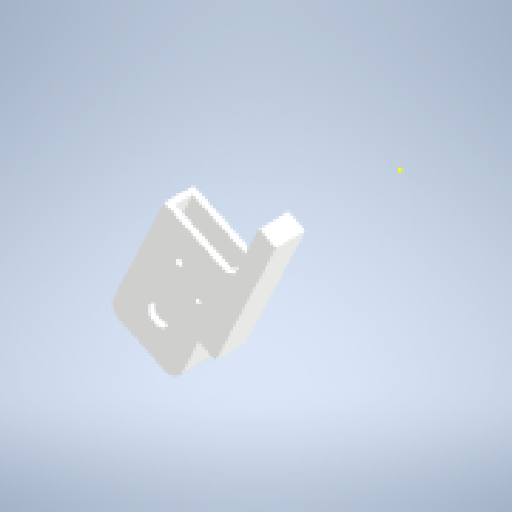
# Autodesk Inventor part: носок
Saved by Autodesk Inventor 2024.2 (Build 282272000, 272)
## iProperties
Created: 2026-10-18
Material: PA-CF
Document SubType Name: Modeling
Designer: katya_notebook
Density: 1.18 g/cm^3
Appearance: Типовые
Author: katya_notebook
Autodesk Inventor part; units mm, degrees
ref_plane "YZ Plane" through (0, 0, 0) normal (1, 0, 0) x (0, 1, 0)
ref_plane "РабПлоскость1" through (0, -0.018426, 0) normal (0, 0, 1) x (1, 0, 0)
sketch "Эскиз1" plane through (0, -0.018426, 0) normal (0, 0, 1) x (1, 0, 0)
  line L0 (-65.689125, -37.064541) -> (-83.531835, -74.877942)
  line L1 (-83.531835, -74.877942) -> (-61.82685, -85.119701)
  line L2 (-61.82685, -85.119701) -> (-43.98414, -47.3063)
  line L3 (-43.98414, -47.3063) -> (-65.689125, -37.064541)
  arc A0 (-77.192404, -71.183023) -> (-58.408034, -73.187635) centre (-67.451778, -68.920236) ccw
  line L4 (-45.566796, -46.559505) -> (-62.556025, -82.564158)
  line L5 (-62.556025, -82.564158) -> (-81.0957, -73.815989)
  line L6 (-81.0957, -73.815989) -> (-64.10647, -37.811336)
  circle A1 centre (-67.451778, -68.920236) radius 10.25
  point P0 (0, 0.018426)
  point P1 (-52.153804, -59.933275)
  point P2 (-45.566796, -46.559505)
  point P3 (-71.825862, -78.190073)
  point P4 (-73.75402, -77.003815)
  point P5 (-76.721615, -64.546151)
  point P6 (-58.181941, -73.29432)
  dimension "d2" = 0
  dimension "d3" = 2
  dimension "d4" = 12.25
  dimension "d5" = 2
  dimension "d20" = 20.5
  dimension "d21" = 10.25
  dimension "d22" = 20.5
  constraints: 14 end point, 3 perpendicular, 2 parallel, 1 centre point, 1 coincident, 1 point on line
  measures "d2" distance from line of L3 L4.start
  measures "d3" distance from line of point (-52.154, -59.933) L2
  measures "d4" distance from line of A0.centre L1
  measures "d5" distance between parallel lines of L1 L5
  measures "d20" diameter of A1
  measures "d21" distance from line of A0.centre L6
  measures "d22" distance between parallel lines of L6 L4
extrude "Выдавливание1" add sketch "Эскиз1" along normal blind 2 and the other way blind 7.5 contours L3 L6 L5 L4 L2 L1 L0
ref_plane "РабПлоскость2" through (0, -0.018426, 0) normal (0, 0, 1) x (1, 0, 0)
sketch "Эскиз2" plane through (0, -0.018426, 2) normal (0, 0, 1) x (1, 0, 0)
  circle A0 centre (-67.451778, -68.920236) radius 2.5
  circle A1 centre (-60.722907, -51.152512) radius 1
  line L0 (-45.566796, -46.559505) -> (-62.556025, -82.564158)
  line L1 (-81.0957, -73.815989) -> (-64.10647, -37.811336)
  circle A2 centre (-67.451778, -68.920236) radius 10.25
  line L2 (-64.10647, -37.811336) -> (-45.566796, -46.559505)
  line L3 (-62.556025, -82.564158) -> (-81.0957, -73.815989)
  point P0 (0, 0.018426)
  point P1 (-62.554737, -82.561427)
  constraints: 2 end point, 1 centre point, 1 coincident, 1 point on line, 1 tangent
sketch "Эскиз4" plane through (0, -0.018426, -7.5) normal (0, 0, -1) x (-1, 0, 0)
  circle A0 centre (60.722907, -51.152512) radius 1
  circle A1 centre (67.451778, -68.920236) radius 2.5
  line L0 (64.10647, -37.811336) -> (81.0957, -73.815989)
  line L1 (81.0957, -73.815989) -> (62.556025, -82.564158)
  line L2 (62.556025, -82.564158) -> (45.566796, -46.559505)
  line L3 (64.10647, -37.811336) -> (45.566796, -46.559505)
  point P0 (0, 0.018426)
  point P1 (45.686204, -46.226727)
  constraints: 2 end point
fillet "Сопряжение1" radius 4 2 edges at (-83.5318, -74.8964, -2.75) (-61.8268, -85.1381, -2.75)
sketch "Эскиз5" plane through (0, -0.018426, -7.5) normal (0, 0, -1) x (-1, 0, 0)
  point P0 (0, 0.018426)
extrude "Выдавливание5" add sketch "Эскиз2" against normal blind 2
extrude "Выдавливание6" add sketch "Эскиз4" against normal blind 2
sketch "Эскиз7" plane through (0, -0.018426, 2) normal (0, 0, 1) x (1, 0, 0)
  line L0 (-60.11989, -81.502204) -> (-43.98414, -47.3063)
  line L1 (-43.98414, -47.3063) -> (-35.449341, -29.218813)
  line L2 (-35.449341, -29.218813) -> (-30.023095, -31.779253)
  line L3 (-30.023095, -31.779253) -> (-49.226393, -72.476099)
  line L4 (-49.226393, -72.476099) -> (-54.652639, -69.91566)
  point P0 (0, 0.018426)
  dimension "d27" = 25
  dimension "d29" = 45
  dimension "d30" = 6
  constraints: 8 end point, 4 perpendicular, 1 point on line
  measures "d27" distance from line of L4 L0.end
  measures "d29" distance between parallel lines of L4 L2
  measures "d30" distance between parallel lines of L3 L0
extrude "Выдавливание7" add sketch "Эскиз7" against normal up to surface (9.5 mm away)
sketch "Эскиз8" plane through (0, -0.018426, 2) normal (0, 0, 1) x (1, 0, 0)
  circle A0 centre (-54.681018, -58.844901) radius 0.75
  line L0 (-43.98414, -47.3063) -> (-65.689125, -37.064541)
  line L1 (-62.556025, -82.564158) -> (-45.566796, -46.559505)
  point P0 (0, 0.018426)
  dimension "d33" = 1.5
  dimension "d34" = 15
  dimension "d35" = 3
  constraints: 1 centre point
  measures "d33" diameter of A0
  measures "d34" distance from line of L0 A0.centre
  measures "d35" distance from line of A0.centre L1
extrude "Выдавливание8" cut sketch "Эскиз8" against normal blind 10
chamfer "Фаска2" distance 2 angle 45 1 edges at (-43.9841, -47.3247, -2.75)
sketch "Эскиз9" plane through (0, -0.018426, 2) normal (0, 0, 1) x (1, 0, 0)
  circle A0 centre (-54.681018, -58.844901) radius 0.75
  circle A1 centre (-60.722907, -51.152512) radius 1
  circle A2 centre (-67.451778, -68.920236) radius 2.5
  arc A3 (-65.444347, -83.412742) -> (-60.11989, -81.502204) centre (-63.737387, -79.795244) ccw
  line L0 (-60.11989, -81.502204) -> (-54.652639, -69.91566)
  line L1 (-54.652639, -69.91566) -> (-49.226393, -72.476099)
  line L2 (-49.226393, -72.476099) -> (-30.023095, -31.779253)
  line L3 (-30.023095, -31.779253) -> (-35.449341, -29.218813)
  line L4 (-35.449341, -29.218813) -> (-43.130661, -45.497552)
  line L5 (-45.792889, -46.45282) -> (-43.130661, -45.497552)
  line L6 (-45.792889, -46.45282) -> (-65.689125, -37.064541)
  line L7 (-65.689125, -37.064541) -> (-81.824875, -71.260445)
  arc A4 (-81.824875, -71.260445) -> (-79.914337, -76.584902) centre (-78.207377, -72.967405) ccw
  line L8 (-79.914337, -76.584902) -> (-65.444347, -83.412742)
  circle A5 centre (-67.451778, -68.920236) radius 3.25
  point P0 (0, 0.018426)
  dimension "d41" = 6.5
  constraints: 1 centre point, 1 coincident
  measures "d41" diameter of A5
extrude "Выдавливание9" cut sketch "Эскиз9" against normal blind 10 contours A2 | A5
